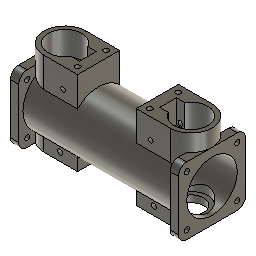
hub (Autodesk Fusion 360 design; units mm, degrees)
part number: 2026-03-27-13-33-24-088
Autodesk Fusion 360 part; units mm, degrees
sketch "Sketch1" plane through (0, 0, 0) normal (1, 0, 0) x (0, 1, 0)
  circle A0 centre (0, 0) radius 15
  circle A1 centre (0, 0) radius 17.5
  constraint coincident A0.centre A1.centre
  constraint concentric A0 A1
extrude "Extrude1" add sketch "Sketch1" along normal blind 50
extrude "Extrude2" add 1 faces at (0, 6.9889, -15.0815) along direction (-1, 0, 0) blind 50
sketch "Sketch3" plane through (-50, 0, 0) normal (-1, 0, 0) x (0, -1, 0)
  circle A0 centre (0, 0) radius 15
  circle A1 centre (0, 0) radius 17.5
  circle A2 centre (0, 0) radius 15
  line L0 (-15, 20) -> (15, 20)
  line L1 (20, 15) -> (20, -15)
  line L2 (15, -20) -> (-15, -20)
  line L3 (-20, -15) -> (-20, 15)
  line L4 (-20, 20) -> (20, -20) construction
  line L5 (20, 20) -> (-20, -20) construction
  arc A3 (-15, 20) -> (-20, 15) centre (-15, 15) ccw
  arc A4 (20, 15) -> (15, 20) centre (15, 15) ccw
  arc A5 (15, -20) -> (20, -15) centre (15, -15) ccw
  arc A6 (-20, -15) -> (-15, -20) centre (-15, -15) ccw
  circle A7 centre (-15, 15) radius 1.5
  circle A8 centre (15, 15) radius 1.5
  circle A9 centre (15, -15) radius 1.5
  circle A10 centre (-15, -15) radius 1.5
  constraint coincident A0.centre A1.centre
  constraint horizontal L0
  constraint perpendicular L0 L1
  constraint parallel L0 L2
  constraint parallel L1 L3
  constraint coincident L4 A0.centre
  constraint coincident L5 A0.centre
  constraint coincident L4.start L0
  constraint coincident L4.start L3
  constraint tangent L0 A3
  constraint tangent L3 A3
  constraint coincident L5.start L0
  constraint coincident L5.start L1
  constraint tangent L0 A4
  constraint tangent L1 A4
  constraint coincident L4.end L1
  constraint coincident L4.end L2
  constraint tangent L1 A5
  constraint tangent L2 A5
  constraint equal A4 A5
  constraint coincident L5.end L2
  constraint coincident L5.end L3
  constraint tangent L2 A6
  constraint tangent L3 A6
  constraint equal A4 A6
  constraint concentric A3 A7
  constraint concentric A4 A8
  constraint concentric A5 A9
  constraint concentric A6 A10
  constraint equal A7 A8
  constraint equal A8 A10
  constraint equal A9 A10
extrude "Extrude3" add sketch "Sketch3" against normal blind 5 contours L0 L1 L2 L3 A3 A4 A5 A6
mirror "Mirror1" about plane through (0, 0, 0) normal (1, 0, 0) of "Extrude3"
sketch "Sketch4" plane through (0, 0, 0) normal (0, 0, 1) x (1, 0, 0)
  circle A0 centre (-37.5, 0) radius 12.5
  line L0 (-50, 15) -> (-50, -15)
  circle A1 centre (-37.5, 0) radius 10
  constraint tangent A0 L0
  constraint concentric A0 A1
extrude "Extrude4" add sketch "Sketch4" along normal up to surface (20 mm away) contours A0 | A1
sketch "Sketch5" plane through (0, 0, 20) normal (0, 0, 1) x (-1, 0, 0)
  line L0 (45, -10) -> (45, -15)
  line L1 (45, -15) -> (50, -15)
  line L2 (50, -15) -> (50, 15)
  line L3 (50, 15) -> (45, 15)
  line L4 (45, 15) -> (45, 10)
  arc A0 (45, 10) -> (45, -10) centre (37.5, 0) ccw
  circle A1 centre (37.5, 0) radius 10
  constraint concentric A0 A1
extrude "Extrude5" cut sketch "Sketch5" against normal blind 5 contours A1
sketch "Sketch6" plane through (0, 0, 20) normal (0, 0, 1) x (-1, 0, 0)
  circle A0 centre (37.5, 0) radius 10
  line L0 (45, -10) -> (45, -15)
  line L1 (45, -15) -> (50, -15)
  line L2 (50, -15) -> (50, 15)
  line L3 (50, 15) -> (45, 15)
  line L4 (45, 15) -> (45, 10)
  arc A1 (45, 10) -> (45, -10) centre (37.5, 0) ccw
  arc A2 (45, 10) -> (45, -10) centre (37.5, 0) ccw
  line L5 (37.5, -12.5) -> (17.5, -12.5)
  line L6 (37.5, 12.5) -> (17.5, 12.5)
  line L7 (17.5, -12.5) -> (17.5, 12.5)
  constraint coincident A2 L5.start
  constraint horizontal L5
  constraint tangent A1 L5
  constraint coincident A1 L6.start
  constraint parallel L5 L6
  constraint tangent A2 L6
  constraint perpendicular L6 L7
extrude "Extrude6" add sketch "Sketch6" along normal up to surface contours A1 A2 L5 L6 L7 end surface at (15, -15.1577, 8.7461)
sketch "Sketch7" plane through (0, 0, 20) normal (0, 0, 1) x (-1, 0, 0)
  circle A0 centre (37.5, 0) radius 10
  line L0 (45, -10) -> (45, -15)
  line L1 (45, -15) -> (50, -15)
  line L2 (50, -15) -> (50, 15)
  line L3 (50, 15) -> (45, 15)
  line L4 (45, 15) -> (45, 10)
  arc A1 (45, 10) -> (37.5, 12.5) centre (37.5, 0) ccw
  line L5 (37.5, 12.5) -> (17.5, 12.5)
  line L6 (17.5, 12.5) -> (17.5, -12.5)
  line L7 (17.5, -12.5) -> (37.5, -12.5)
  arc A2 (37.5, -12.5) -> (45, -10) centre (37.5, 0) ccw
  line L8 (28.8397, -5) -> (23.8397, -5)
  line L9 (23.8397, -5) -> (23.8397, 5)
  line L10 (23.8397, 5) -> (28.8397, 5)
  line L11 (28.8397, 5) -> (28.8397, -5)
  constraint horizontal L8
  constraint vertical L9
  constraint horizontal L10
  constraint vertical L11
  constraint coincident A0 L8.start
extrude "Extrude7" cut sketch "Sketch7" against normal up to surface (5 mm away) contours A0 L8 L9 L10
sketch "Sketch8" plane through (-50, 0, 0) normal (-1, 0, 0) x (0, -1, 0)
  line L0 (15, 20) -> (-15, 20)
  arc A0 (-15, 20) -> (-20, 15) centre (-15, 15) ccw
  line L1 (-20, 15) -> (-20, -15)
  arc A1 (-20, -15) -> (-15, -20) centre (-15, -15) ccw
  line L2 (-15, -20) -> (15, -20)
  arc A2 (15, -20) -> (20, -15) centre (15, -15) ccw
  line L3 (20, -15) -> (20, 15)
  arc A3 (20, 15) -> (15, 20) centre (15, 15) ccw
  circle A4 centre (0, 0) radius 15
  circle A5 centre (-15, 15) radius 1.5
  circle A6 centre (-15, -15) radius 1.5
  circle A7 centre (15, 15) radius 1.5
  circle A8 centre (15, -15) radius 1.5
extrude "Extrude8" cut sketch "Sketch8" against normal blind 101 contours A4
sketch "Sketch9" plane through (0, 0, 20) normal (0, 0, 1) x (-1, 0, 0)
  line L0 (45, -10) -> (45, -15)
  line L1 (45, -15) -> (50, -15)
  line L2 (50, -15) -> (50, 15)
  line L3 (50, 15) -> (45, 15)
  line L4 (45, 15) -> (45, 10)
  arc A0 (45, 10) -> (37.5, 12.5) centre (37.5, 0) ccw
  line L5 (37.5, 12.5) -> (17.5, 12.5)
  line L6 (17.5, 12.5) -> (17.5, -12.5)
  line L7 (17.5, -12.5) -> (37.5, -12.5)
  arc A1 (37.5, -12.5) -> (45, -10) centre (37.5, 0) ccw
  line L8 (28.8397, -5) -> (23.8397, -5)
  line L9 (23.8397, -5) -> (23.8397, 5)
  line L10 (23.8397, 5) -> (28.8397, 5)
  arc A2 (28.8397, -5) -> (28.8397, 5) centre (37.5, 0) ccw
  circle A3 centre (37.5, 0) radius 7.433
  constraint concentric A0 A3
extrude "Extrude9" cut sketch "Sketch9" against normal blind 8 contours A3
extrude "Extrude10" add 1 faces at (-25.8932, 3.3333, 15) along direction (0, 0, 1) blind 1
extrude "Extrude11" add 1 faces at (-25.5064, -3.3333, 15) along direction (0, 0, 1) blind 1
sketch "Sketch10" plane through (0, 5, 0) normal (0, -1, 0) x (1, 0, 0)
  line L0 (-28.8397, 16) -> (-23.8397, 16)
  line L1 (-23.8397, 16) -> (-23.8397, 20)
  line L2 (-23.8397, 20) -> (-28.8397, 20)
  line L3 (-28.8397, 20) -> (-28.8397, 16)
  line L4 (-28.8397, 20) -> (-23.3767, 20)
  line L5 (-23.3767, 20) -> (-23.3767, 16)
  line L6 (-23.3767, 16) -> (-28.8397, 16)
  line L7 (-28.8397, 16) -> (-28.8397, 20)
  line L8 (-28.8397, 20) -> (-23.3767, 16) construction
  line L9 (-23.3767, 20) -> (-28.8397, 16) construction
  circle A0 centre (-26.1082, 18) radius 1.3481
  point P0 (-26.1082, 18)
  constraint horizontal L4
  constraint perpendicular L4 L5
  constraint parallel L4 L6
  constraint parallel L5 L7
  constraint coincident L8 P0
  constraint coincident L9 P0
  constraint coincident L2.end L3.start
  constraint coincident L0 L3.end
  constraint coincident P0 A0.centre
extrude "Extrude12" cut sketch "Sketch10" along normal blind 18 and the other way blind 8 contours A0
mirror "Mirror2" about plane through (0, 0, 0) normal (1, 0, 0) of "Extrude4", "Extrude5", "Extrude6", "Extrude7", "Extrude8", "Extrude9", "Extrude10", "Extrude11", "Extrude12"
sketch "Sketch11" plane through (0, 0, 0) normal (0, 0, 1) x (1, 0, 0)
  line L0 (-50, -15) -> (-50, 15)
  line L1 (-37.5, -12.5) -> (-17.5, -12.5)
  line L2 (-17.5, -12.5) -> (-17.5, 12.5)
  line L3 (-17.5, 12.5) -> (-37.5, 12.5)
  arc A0 (-37.5, 12.5) -> (-37.5, -12.5) centre (-37.5, 0) ccw
  line L4 (-28.8397, -5) -> (-23.8397, -5)
  line L5 (-23.8397, -5) -> (-23.8397, 5)
  line L6 (-23.8397, 5) -> (-28.8397, 5)
  arc A1 (-28.8397, 5) -> (-28.8397, -5) centre (-37.5, 0) ccw
  constraint tangent L0 A0
  constraint concentric A0 A1
  constraint horizontal L1
  constraint vertical L2
  constraint horizontal L3
  constraint tangent L1 A0
  constraint tangent L3 A0
  constraint horizontal L4
  constraint vertical L5
  constraint horizontal L6
extrude "Extrude13" add sketch "Sketch11" against normal up to surface (20 mm away)
sketch "Sketch12" plane through (-50, 0, 0) normal (-1, 0, 0) x (0, -1, 0)
  line L0 (-15, -20) -> (15, -20)
  arc A0 (15, -20) -> (20, -15) centre (15, -15) ccw
  line L1 (20, -15) -> (20, 15)
  arc A1 (20, 15) -> (15, 20) centre (15, 15) ccw
  line L2 (15, 20) -> (-15, 20)
  arc A2 (-15, 20) -> (-20, 15) centre (-15, 15) ccw
  line L3 (-20, 15) -> (-20, -15)
  arc A3 (-20, -15) -> (-15, -20) centre (-15, -15) ccw
  circle A4 centre (0, 0) radius 15
  circle A5 centre (-15, 15) radius 1.5
  circle A6 centre (-15, -15) radius 1.5
  circle A7 centre (15, 15) radius 1.5
  circle A8 centre (15, -15) radius 1.5
extrude "Extrude14" cut sketch "Sketch12" against normal blind 103 contours A4
sketch "Sketch13" plane through (0, 0, -20) normal (0, 0, -1) x (1, 0, 0)
  line L0 (-45, 10) -> (-45, 15)
  line L1 (-45, 15) -> (-50, 15)
  line L2 (-50, 15) -> (-50, -15)
  line L3 (-50, -15) -> (-45, -15)
  line L4 (-45, -15) -> (-45, -10)
  arc A0 (-45, -10) -> (-37.5, -12.5) centre (-37.5, 0) ccw
  line L5 (-37.5, -12.5) -> (-17.5, -12.5)
  line L6 (-17.5, -12.5) -> (-17.5, 12.5)
  line L7 (-17.5, 12.5) -> (-37.5, 12.5)
  arc A1 (-37.5, 12.5) -> (-45, 10) centre (-37.5, 0) ccw
  arc A2 (-28.8397, 5) -> (-45, 6.6144) centre (-37.5, 0) ccw
  line L8 (-28.8397, 5) -> (-23.8397, 5)
  line L9 (-23.8397, 5) -> (-23.8397, -5)
  line L10 (-23.8397, -5) -> (-28.8397, -5)
  arc A3 (-45, -6.6144) -> (-28.8397, -5) centre (-37.5, 0) ccw
  line L11 (-45, -6.6144) -> (-45, 6.6144)
  circle A4 centre (-37.5, 0) radius 10
  constraint concentric A0 A4
extrude "Extrude15" cut sketch "Sketch13" against normal blind 7 contours A2 A3 L11 A4 | L11 A4
sketch "Sketch14" plane through (0, 0, -20) normal (0, 0, -1) x (1, 0, 0)
  arc A0 (-28.8397, 5) -> (-28.8397, -5) centre (-37.5, 0) ccw
  line L0 (-28.8397, 5) -> (-23.8397, 5)
  line L1 (-23.8397, 5) -> (-23.8397, -5)
  line L2 (-23.8397, -5) -> (-28.8397, -5)
  line L3 (-45, 10) -> (-45, 15)
  line L4 (-45, 15) -> (-50, 15)
  line L5 (-50, 15) -> (-50, -15)
  line L6 (-50, -15) -> (-45, -15)
  line L7 (-45, -15) -> (-45, -10)
  arc A1 (-45, -10) -> (-37.5, -12.5) centre (-37.5, 0) ccw
  line L8 (-37.5, -12.5) -> (-17.5, -12.5)
  line L9 (-17.5, -12.5) -> (-17.5, 12.5)
  line L10 (-17.5, 12.5) -> (-37.5, 12.5)
  arc A2 (-37.5, 12.5) -> (-45, 10) centre (-37.5, 0) ccw
  line L11 (-28.8397, 5) -> (-26.8397, 5)
  line L12 (-26.8397, 5) -> (-26.8397, -5)
  line L13 (-26.8397, -5) -> (-28.8397, -5)
  line L14 (-28.8397, -5) -> (-28.8397, 5)
  constraint horizontal L11
  constraint vertical L12
  constraint horizontal L13
  constraint vertical L14
  constraint coincident L2 L12.end
  constraint coincident A0.start L0.start
extrude "Extrude16" cut sketch "Sketch14" against normal blind 9 contours L0 L2 L11 L12 L13 L14
sketch "Sketch15" plane through (0, 0, -20) normal (0, 0, -1) x (1, 0, 0)
  arc A0 (-28.8397, 5) -> (-28.8397, -5) centre (-37.5, 0) ccw
  line L0 (-28.8397, 5) -> (-23.8397, 5)
  line L1 (-23.8397, 5) -> (-23.8397, -5)
  line L2 (-23.8397, -5) -> (-28.8397, -5)
  line L3 (-45, 10) -> (-45, 15)
  line L4 (-45, 15) -> (-50, 15)
  line L5 (-50, 15) -> (-50, -15)
  line L6 (-50, -15) -> (-45, -15)
  line L7 (-45, -15) -> (-45, -10)
  arc A1 (-45, -10) -> (-37.5, -12.5) centre (-37.5, 0) ccw
  line L8 (-37.5, -12.5) -> (-17.5, -12.5)
  line L9 (-17.5, -12.5) -> (-17.5, 12.5)
  line L10 (-17.5, 12.5) -> (-37.5, 12.5)
  arc A2 (-37.5, 12.5) -> (-45, 10) centre (-37.5, 0) ccw
  circle A3 centre (-37.5, 0) radius 7.5
  arc A4 (-28.8397, 5) -> (-28.8397, -5) centre (-37.5, 0) ccw
  line L11 (-23.8397, 5) -> (-28.8397, 5)
  line L12 (-23.8397, -5) -> (-23.8397, 5)
  line L13 (-28.8397, -5) -> (-23.8397, -5)
  constraint concentric A0 A3
extrude "Extrude17" add sketch "Sketch15" against normal blind 4 contours A0 L0 L1 L2 A4 L11 L12 L13
extrude "Extrude18" cut 2 faces at (-39.0496, 7.9401, -13) (-38.298, -8.2253, -13) along direction (0, 0, 1) blind 4
sketch "Sketch16" plane through (0, 5, 0) normal (0, -1, 0) x (1, 0, 0)
  line L0 (-28.8397, -16) -> (-26.8397, -16)
  line L1 (-26.8397, -16) -> (-26.8397, -14.1421)
  line L2 (-26.8397, -14.1421) -> (-28.8397, -14.1421)
  line L3 (-28.8397, -14.1421) -> (-28.8397, -16)
  line L4 (-28.8397, -14.1421) -> (-26.8397, -14.1421)
  line L5 (-26.8397, -14.1421) -> (-26.8397, -16)
  line L6 (-26.8397, -16) -> (-28.8397, -16)
  line L7 (-28.8397, -16) -> (-28.8397, -14.1421)
  line L8 (-28.8397, -14.1421) -> (-26.8397, -16) construction
  line L9 (-26.8397, -14.1421) -> (-28.8397, -16) construction
  circle A0 centre (-27.8397, -15.0711) radius 1.5
  point P0 (-27.8397, -15.0711)
  constraint horizontal L4
  constraint perpendicular L4 L5
  constraint parallel L4 L6
  constraint parallel L5 L7
  constraint coincident L8 P0
  constraint coincident L9 P0
  constraint coincident L2.end L3.start
  constraint coincident P0 A0.centre
extrude "Extrude19" cut sketch "Sketch16" along normal blind 20 and the other way blind 25 contours L0 L1 L2 L3 L4 L5 L6 L7 | A0
mirror "Mirror3" about plane through (0, 0, 0) normal (1, 0, 0) of "Extrude13", "Extrude14", "Extrude15", "Extrude16", "Extrude17", "Extrude18", "Extrude19"
sketch "Sketch17" plane through (-50, 0, 0) normal (-1, 0, 0) x (0, -1, 0)
  line L0 (-15, -20) -> (15, -20)
  arc A0 (15, -20) -> (20, -15) centre (15, -15) ccw
  line L1 (20, -15) -> (20, 15)
  arc A1 (20, 15) -> (15, 20) centre (15, 15) ccw
  line L2 (15, 20) -> (-15, 20)
  arc A2 (-15, 20) -> (-20, 15) centre (-15, 15) ccw
  line L3 (-20, 15) -> (-20, -15)
  arc A3 (-20, -15) -> (-15, -20) centre (-15, -15) ccw
  circle A4 centre (0, 0) radius 15
  circle A5 centre (-15, 15) radius 1.5
  circle A6 centre (-15, -15) radius 1.5
  circle A7 centre (15, 15) radius 1.5
  circle A8 centre (15, -15) radius 1.5
  circle A9 centre (0, 0) radius 15
  constraint coincident A4.centre A9.centre
extrude "Extrude20" add sketch "Sketch17" against normal blind 2 contours A4 A9
sketch "Sketch18" plane through (0, 0, 20) normal (0, 0, 1) x (-1, 0, 0)
  line L0 (-45, 10) -> (-45, 15)
  line L1 (-45, 15) -> (-50, 15)
  line L2 (-50, 15) -> (-50, -15)
  line L3 (-50, -15) -> (-45, -15)
  line L4 (-45, -15) -> (-45, -10)
  arc A0 (-45, -10) -> (-37.5, -12.5) centre (-37.5, 0) ccw
  line L5 (-37.5, -12.5) -> (-17.5, -12.5)
  line L6 (-17.5, -12.5) -> (-17.5, 12.5)
  line L7 (-17.5, 12.5) -> (-37.5, 12.5)
  arc A1 (-37.5, 12.5) -> (-45, 10) centre (-37.5, 0) ccw
  line L8 (-28.8397, 5) -> (-23.8397, 5)
  line L9 (-23.8397, 5) -> (-23.8397, -5)
  line L10 (-23.8397, -5) -> (-28.8397, -5)
  arc A2 (-28.8397, 5) -> (-28.8397, -5) centre (-37.5, 0) ccw
  circle A3 centre (-37.5, 0) radius 7.433
  line L11 (-23.8397, -5) -> (-23.8397, 5)
  line L12 (-23.8397, 5) -> (-28.8397, 5)
  arc A4 (-28.8397, 5) -> (-28.8397, -5) centre (-37.5, 0) ccw
  line L13 (-28.8397, -5) -> (-23.8397, -5)
  line L14 (23.8397, 5) -> (23.8397, -5)
  line L15 (23.8397, -5) -> (28.8397, -5)
  arc A5 (28.8397, -5) -> (28.8397, 5) centre (37.5, 0) ccw
  line L16 (28.8397, 5) -> (23.8397, 5)
  circle A6 centre (37.5, 0) radius 7.433
  line L17 (45, -10) -> (45, -15)
  line L18 (45, -15) -> (50, -15)
  line L19 (50, -15) -> (50, 15)
  line L20 (50, 15) -> (45, 15)
  line L21 (45, 15) -> (45, 10)
  arc A7 (45, 10) -> (37.5, 12.5) centre (37.5, 0) ccw
  line L22 (37.5, 12.5) -> (17.5, 12.5)
  line L23 (17.5, 12.5) -> (17.5, -12.5)
  line L24 (17.5, -12.5) -> (37.5, -12.5)
  arc A8 (37.5, -12.5) -> (45, -10) centre (37.5, 0) ccw
  line L25 (28.8397, -5) -> (23.8397, -5)
  line L26 (23.8397, -5) -> (23.8397, 5)
  line L27 (23.8397, 5) -> (28.8397, 5)
  arc A9 (28.8397, -5) -> (28.8397, 5) centre (37.5, 0) ccw
  circle A10 centre (37.5, 0) radius 12.5
  circle A11 centre (-37.5, 0) radius 10
  circle A12 centre (-37.5, 0) radius 12.5
  constraint concentric A5 A10
  constraint coincident L17.start A10
  constraint concentric A3 A11
  constraint concentric A3 A12
  constraint coincident L0.start A12
extrude "Extrude21" add sketch "Sketch18" along normal blind 10 contours A0 A1 L8 L10 A2 L12 A4 L13 A11 A12 | L5 L6 L7 L8 L9 L10 L11 L12 L13 A12 | L14 L15 L16 L22 L23 L24 L25 L26 L27 A10 | L15 A5 L16 A7 A8 L25 L27 A9 A10
sketch "Sketch19" plane through (0, 0, 30) normal (0, 0, 1) x (-1, 0, 0)
  line L0 (28.8397, -5) -> (23.8397, -5)
  line L1 (23.8397, -5) -> (23.8397, 5)
  line L2 (23.8397, 5) -> (28.8397, 5)
  arc A0 (28.8397, -5) -> (28.8397, 5) centre (37.5, 0) ccw
  arc A1 (37.5, -12.5) -> (37.5, 12.5) centre (37.5, 0) ccw
  line L3 (37.5, 12.5) -> (17.5, 12.5)
  line L4 (17.5, 12.5) -> (17.5, -12.5)
  line L5 (17.5, -12.5) -> (37.5, -12.5)
  line L6 (-28.8397, 5) -> (-23.8397, 5)
  line L7 (-23.8397, 5) -> (-23.8397, -5)
  line L8 (-23.8397, -5) -> (-28.8397, -5)
  arc A2 (-28.8397, 5) -> (-28.8397, -5) centre (-37.5, 0) ccw
  line L9 (-17.5, 12.5) -> (-37.5, 12.5)
  arc A3 (-37.5, 12.5) -> (-37.5, -12.5) centre (-37.5, 0) ccw
  line L10 (-37.5, -12.5) -> (-17.5, -12.5)
  line L11 (-17.5, -12.5) -> (-17.5, 12.5)
  arc A4 (37.5, -8.5) -> (37.5, 8.5) centre (37.5, 0) ccw
  line L12 (37.5, 8.5) -> (21.5, 8.5)
  line L13 (21.5, 8.5) -> (21.5, -8.5)
  line L14 (21.5, -8.5) -> (37.5, -8.5)
  line L15 (-21.5, 8.5) -> (-37.5, 8.5)
  arc A5 (-37.5, 8.5) -> (-37.5, -8.5) centre (-37.5, 0) ccw
  line L16 (-37.5, -8.5) -> (-21.5, -8.5)
  line L17 (-21.5, -8.5) -> (-21.5, 8.5)
  circle A6 centre (21.5, -8.5) radius 1.5
  circle A7 centre (21.5, 8.5) radius 1.5
  circle A8 centre (-21.5, -8.5) radius 1.5
  circle A9 centre (-21.5, 8.5) radius 1.5
  constraint coincident L13.end L14.start
  constraint coincident L12.end L13.start
  constraint coincident L16.end L17.start
  constraint coincident L15.start L17.end
  constraint equal A6 A8
  constraint equal A8 A9
  constraint equal A7 A9
extrude "Extrude22" cut sketch "Sketch19" against normal blind 5 contours L13 L14 A6 | L13 L14 A6 | L12 L13 A7 | L12 L13 A7 | L15 L17 A9 | L15 L17 A9 | L16 L17 A8 | L16 L17 A8
sketch "Sketch20" plane through (0, 0, -20) normal (0, 0, -1) x (1, 0, 0)
  circle A0 centre (37.5, 0) radius 7.5
  line L0 (45, -10) -> (45, -15)
  line L1 (45, -15) -> (50, -15)
  line L2 (50, -15) -> (50, 15)
  line L3 (50, 15) -> (45, 15)
  line L4 (45, 15) -> (45, 10)
  arc A1 (45, 10) -> (37.5, 12.5) centre (37.5, 0) ccw
  line L5 (37.5, 12.5) -> (17.5, 12.5)
  line L6 (17.5, 12.5) -> (17.5, -12.5)
  line L7 (17.5, -12.5) -> (37.5, -12.5)
  arc A2 (37.5, -12.5) -> (45, -10) centre (37.5, 0) ccw
  circle A3 centre (-37.5, 0) radius 7.5
  line L8 (-45, 10) -> (-45, 15)
  line L9 (-45, 15) -> (-50, 15)
  line L10 (-50, 15) -> (-50, -15)
  line L11 (-50, -15) -> (-45, -15)
  line L12 (-45, -15) -> (-45, -10)
  arc A4 (-45, -10) -> (-37.5, -12.5) centre (-37.5, 0) ccw
  line L13 (-37.5, -12.5) -> (-17.5, -12.5)
  line L14 (-17.5, -12.5) -> (-17.5, 12.5)
  line L15 (-17.5, 12.5) -> (-37.5, 12.5)
  arc A5 (-37.5, 12.5) -> (-45, 10) centre (-37.5, 0) ccw
  arc A6 (37.5, -8.5) -> (42.6, -6.8) centre (37.5, 0) ccw
  arc A7 (46, -6.127) -> (42.6, -6.8) centre (45, -10) ccw
  line L16 (46, -6.127) -> (46, 6.127)
  arc A8 (42.6, 6.8) -> (46, 6.127) centre (45, 10) ccw
  arc A9 (42.6, 6.8) -> (37.5, 8.5) centre (37.5, 0) ccw
  line L17 (37.5, 8.5) -> (21.5, 8.5)
  line L18 (21.5, 8.5) -> (21.5, -8.5)
  line L19 (21.5, -8.5) -> (37.5, -8.5)
  arc A10 (-37.5, 8.5) -> (-42.6, 6.8) centre (-37.5, 0) ccw
  arc A11 (-46, 6.127) -> (-42.6, 6.8) centre (-45, 10) ccw
  line L20 (-46, 6.127) -> (-46, -6.127)
  arc A12 (-42.6, -6.8) -> (-46, -6.127) centre (-45, -10) ccw
  arc A13 (-42.6, -6.8) -> (-37.5, -8.5) centre (-37.5, 0) ccw
  line L21 (-37.5, -8.5) -> (-21.5, -8.5)
  line L22 (-21.5, -8.5) -> (-21.5, 8.5)
  line L23 (-21.5, 8.5) -> (-37.5, 8.5)
  circle A14 centre (21.5, -8.5) radius 1.5
  circle A15 centre (21.5, 8.5) radius 1.5
  circle A16 centre (-21.5, -8.5) radius 1.5
  circle A17 centre (-21.5, 8.5) radius 1.5
  constraint coincident L18.end L19.start
  constraint coincident L17.end L18.start
  constraint coincident L21.end L22.start
  constraint coincident L22.end L23.start
  constraint equal A14 A15
  constraint equal A15 A17
  constraint equal A16 A17
extrude "Extrude23" cut sketch "Sketch20" against normal blind 5 contours L18 L19 A14 | L18 L19 A14 | L17 L18 A15 | L17 L18 A15 | L22 L23 A17 | L22 L23 A17 | L21 L22 A16 | L21 L22 A16
